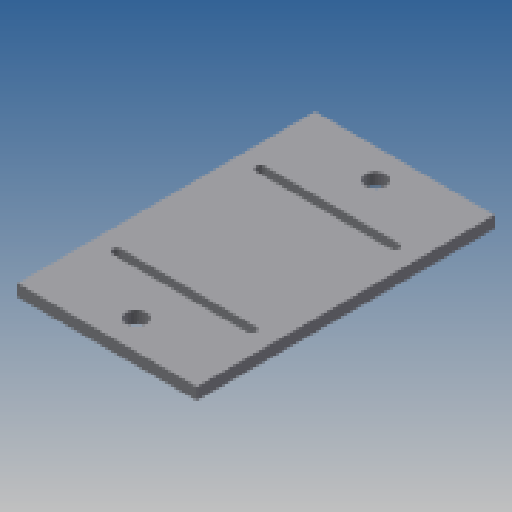
# Autodesk Inventor part: supportchargeur
Saved by Autodesk Inventor 2025.3 (Build 293356000, 356)
## iProperties
Created: 2025-06-22
Part Number: supportchargeur
Project: Nom Projet
Material: .
Description: Nom pièce
Document SubType Name: Modeling
Designer: matpo
Authority: brut Ø
Density: 0.001 g/cm^3
Appearance: Par défaut
Author: matpo
Material number: ---
Autodesk Inventor part; units mm, degrees
ref_plane "Plan YZ" through (0, 0, 0) normal (1, 0, 0) x (0, 1, 0)
ref_plane "Plan XZ" through (0, 0, 0) normal (0, 1, 0) x (-1, 0, 0)
ref_plane "Plan XY" through (0, 0, 0) normal (0, 0, 1) x (1, 0, 0)
sketch "Esquisse1" plane through (0, 0, 0) normal (0, 0, 1) x (1, 0, 0)
  circle A0 centre (0, 20) radius 1.7 projected
  circle A1 centre (0, -20) radius 1.7 projected
  line L0 (33.8598, 24.875) -> (-17.4476, 24.875) projected
  line L1 (33.8598, -24.875) -> (-17.4476, -24.875) projected
  line L2 (-15, 24.875) -> (15, 24.875)
  line L3 (15, 24.875) -> (15, -24.875)
  line L4 (15, -24.875) -> (-15, -24.875)
  line L5 (-15, -24.875) -> (-15, 24.875)
  line L6 (-15, 0) -> (0, 0) construction
  line L7 (0, 0) -> (15, 0) construction
  circle A2 centre (-11.25, 12) radius 0.75 construction
  circle A3 centre (11.25, 12) radius 0.75 construction
  line L8 (11.25, 11.25) -> (-11.25, 11.25)
  line L9 (-11.25, 12.75) -> (11.25, 12.75)
  line L10 (-11.25, 12) -> (0, 12) construction
  line L11 (0, 12) -> (11.25, 12) construction
  arc A4 (-11.25, 12.75) -> (-11.25, 11.25) centre (-11.25, 12) ccw
  arc A5 (11.25, 11.25) -> (11.25, 12.75) centre (11.25, 12) ccw
  circle A6 centre (-11.25, -12) radius 0.75 construction
  circle A7 centre (11.25, -12) radius 0.75 construction
  line L12 (11.25, -11.25) -> (-11.25, -11.25)
  line L13 (-11.25, -12.75) -> (11.25, -12.75)
  line L14 (-11.25, -12) -> (0, -12) construction
  line L15 (0, -12) -> (11.25, -12) construction
  arc A8 (-11.25, -11.25) -> (-11.25, -12.75) centre (-11.25, -12) ccw
  arc A9 (11.25, -12.75) -> (11.25, -11.25) centre (11.25, -12) ccw
  point P0 (15, 24.875)
  dimension "d0" = 30
  dimension "d1" = 1.5
  dimension "d2" = 24
  dimension "d3" = 12
  constraints: 28 end point, 18 point on circle, 10 symmetric about line, 8 centre point, 5 tangent, 4 equal length, 4 horizontal, 2 collinear, 2 midpoint, 2 perpendicular, 2 point on line, 1 equal radius, 1 horizontal alignment, 1 vertical alignment, 4 other
  measures "d0" distance between parallel lines of L3 L5
  measures "d1" distance between parallel lines of L8 L9
  measures "d3" distance from line of L6.end L10
sketch "Esquisse6" plane through (0, 0, 0) normal (0, 0, 1) x (1, 0, 0)
  point P0 (0, 0)
extrude "Extrusion1" add sketch "Esquisse1" along normal blind 2
sketch "Esquisse7" plane through (0, 0, 2) normal (0, 0, 1) x (1, 0, 0)
  circle A0 centre (0, 20) radius 1.7 projected
  circle A1 centre (0, -20) radius 1.7 projected
  point P0 (0, 0)
hole "Perçage1" at (0, 20, 2) at (0, -20, 2) direction (0, 0, -1) diameter 3.3 depth 20 counterbore diameter 6.5 counterbore depth 1
